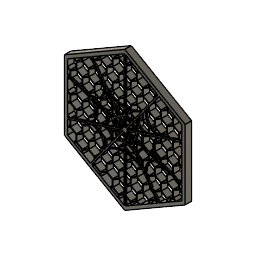
Honey Comb and Web Spider (1) (Autodesk Fusion 360 design; units mm, degrees)
Autodesk Fusion 360 part; units mm, degrees
(part 1 of 3)
sketch "Sketch1" plane through (0, 0, 0) normal (0, 1, 0) x (1, 0, 0)
  line L0 (0, 0) -> (-86.603, 0) construction
  line L1 (-86.603, 0) -> (-86.603, 50) construction
  line L2 (-86.603, 50) -> (-86.603, -50)
  line L3 (-86.603, -50) -> (-0.0005, -100)
  line L4 (-0.0005, -100) -> (86.6021, -50)
  line L5 (86.6021, -50) -> (86.6021, 50)
  line L6 (86.6021, 50) -> (-0.0005, 100)
  line L7 (-0.0005, 100) -> (-86.603, 50)
  line L8 (-0.0005, -100) -> (-0.0005, 0) construction
  line L9 (-0.0005, 0) -> (8.6598, 0) construction
  line L10 (8.6598, 0) -> (8.6598, 5) construction
  line L11 (8.6598, 5) -> (-0.0004, 10)
  line L12 (-0.0004, 10) -> (-8.6607, 5)
  line L13 (-8.6607, 5) -> (-8.6607, -5)
  line L14 (-8.6607, -5) -> (-0.0004, -10)
  line L15 (-0.0004, -10) -> (8.6598, -5)
  line L16 (8.6598, -5) -> (8.6598, 5)
  line L17 (-0.0004, -10) -> (0.4996, -10.866) construction
  line L18 (0.4996, -10.866) -> (0.4996, -20.866)
  line L19 (0.4996, -20.866) -> (9.1598, -25.866)
  line L20 (9.1598, -25.866) -> (17.8201, -20.866)
  line L21 (17.8201, -20.866) -> (17.8201, -10.866)
  line L22 (17.8201, -10.866) -> (9.1598, -5.866)
  line L23 (9.1598, -5.866) -> (0.4996, -10.866)
  line L24 (9.1598, -5.866) -> (9.6598, -5) construction
  line L25 (9.6598, -5) -> (8.6598, -5) construction
  line L26 (9.6598, -5) -> (18.3201, -10)
  line L27 (18.3201, -10) -> (26.9803, -5)
  line L28 (26.9803, -5) -> (26.9803, 5)
  line L29 (26.9803, 5) -> (18.3201, 10)
  line L30 (18.3201, 10) -> (9.6598, 5)
  line L31 (9.6598, 5) -> (9.6598, -5)
  line L32 (18.3201, -10) -> (18.8201, -10.866) construction
  line L33 (18.3201, -10) -> (19.3201, -10) construction
  line L34 (18.8201, -10.866) -> (17.8201, -10.866) construction
  line L35 (26.9803, -5) -> (27.9803, -5) construction
  line L36 (17.8201, -20.866) -> (18.8201, -20.866) construction
  line L37 (18.8201, -20.866) -> (27.4803, -25.866)
  line L38 (27.4803, -25.866) -> (36.1406, -20.866)
  line L39 (36.1406, -20.866) -> (36.1406, -10.866)
  line L40 (36.1406, -10.866) -> (27.4803, -5.866)
  line L41 (27.4803, -5.866) -> (18.8201, -10.866)
  line L42 (18.8201, -10.866) -> (18.8201, -20.866)
  line L43 (27.9803, -5) -> (36.6406, -10)
  line L44 (36.6406, -10) -> (45.3009, -5)
  line L45 (45.3009, -5) -> (45.3009, 5)
  line L46 (45.3009, 5) -> (36.6406, 10)
  line L47 (36.6406, 10) -> (27.9803, 5)
  line L48 (27.9803, 5) -> (27.9803, -5)
  line L49 (17.8201, -20.866) -> (18.3201, -21.7321) construction
  line L50 (18.3201, -21.7321) -> (9.6598, -26.7321) construction
  line L51 (18.3201, -21.7321) -> (9.6598, -26.7321)
  line L52 (9.6598, -26.7321) -> (9.6598, -36.7321)
  line L53 (9.6598, -36.7321) -> (18.3201, -41.7321)
  line L54 (18.3201, -41.7321) -> (26.9803, -36.7321)
  line L55 (26.9803, -36.7321) -> (26.9803, -26.7321)
  line L56 (26.9803, -26.7321) -> (18.3201, -21.7321)
  line L57 (9.6598, -26.7321) -> (8.6598, -26.7321) construction
  line L58 (26.9803, -26.7321) -> (27.9803, -26.7321) construction
  line L59 (36.1406, -20.866) -> (37.1406, -20.866) construction
  line L60 (45.3009, -5) -> (46.3009, -5) construction
  line L61 (46.3009, -5) -> (54.9611, -10)
  line L62 (54.9611, -10) -> (63.6214, -5)
  line L63 (63.6214, -5) -> (63.6214, 5)
  line L64 (63.6214, 5) -> (54.9611, 10)
  line L65 (54.9611, 10) -> (46.3009, 5)
  line L66 (46.3009, 5) -> (46.3009, -5)
  line L67 (37.1406, -20.866) -> (45.8009, -25.866)
  line L68 (45.8009, -25.866) -> (54.4611, -20.866)
  line L69 (54.4611, -20.866) -> (54.4611, -10.866)
  line L70 (54.4611, -10.866) -> (45.8009, -5.866)
  line L71 (45.8009, -5.866) -> (37.1406, -10.866)
  line L72 (37.1406, -10.866) -> (37.1406, -20.866)
  line L73 (27.9803, -26.7321) -> (27.9803, -36.7321)
  line L74 (27.9803, -36.7321) -> (36.6406, -41.7321)
  line L75 (36.6406, -41.7321) -> (45.3009, -36.7321)
  line L76 (45.3009, -36.7321) -> (45.3009, -26.7321)
  line L77 (45.3009, -26.7321) -> (36.6406, -21.7321)
  line L78 (36.6406, -21.7321) -> (27.9803, -26.7321)
  line L79 (8.6598, -26.7321) -> (-0.0004, -21.7321)
  line L80 (-0.0004, -21.7321) -> (-8.6607, -26.7321)
  line L81 (-8.6607, -26.7321) -> (-8.6607, -36.7321)
  line L82 (-8.6607, -36.7321) -> (-0.0004, -41.7321)
  line L83 (-0.0004, -41.7321) -> (8.6598, -36.7321)
  line L84 (8.6598, -36.7321) -> (8.6598, -26.7321)
  line L85 (8.6598, -36.7321) -> (9.1598, -37.5981) construction
  line L86 (26.9803, -36.7321) -> (27.4803, -37.5981) construction
  line L87 (45.3009, -36.7321) -> (45.8009, -37.5981) construction
  line L88 (45.3009, -36.7321) -> (46.3009, -36.7321) construction
  line L89 (54.4611, -20.866) -> (55.4611, -20.866) construction
  line L90 (63.6214, -5) -> (64.6214, -5) construction
  line L91 (64.6214, -5) -> (73.2816, -10)
  line L92 (73.2816, -10) -> (81.9419, -5)
  line L93 (81.9419, -5) -> (81.9419, 5)
  line L94 (81.9419, 5) -> (73.2816, 10)
  line L95 (73.2816, 10) -> (64.6214, 5)
  line L96 (64.6214, 5) -> (64.6214, -5)
  line L97 (55.4611, -20.866) -> (64.1214, -25.866)
  line L98 (64.1214, -25.866) -> (72.7816, -20.866)
  line L99 (72.7816, -20.866) -> (72.7816, -10.866)
  line L100 (72.7816, -10.866) -> (64.1214, -5.866)
  line L101 (64.1214, -5.866) -> (55.4611, -10.866)
  line L102 (55.4611, -10.866) -> (55.4611, -20.866)
  line L103 (46.3009, -36.7321) -> (54.9611, -41.7321)
  line L104 (54.9611, -41.7321) -> (63.6214, -36.7321)
  line L105 (63.6214, -36.7321) -> (63.6214, -26.7321)
  line L106 (63.6214, -26.7321) -> (54.9611, -21.7321)
  line L107 (54.9611, -21.7321) -> (46.3009, -26.7321)
  line L108 (46.3009, -26.7321) -> (46.3009, -36.7321)
  line L109 (45.8009, -37.5981) -> (37.1406, -42.5981)
  line L110 (37.1406, -42.5981) -> (37.1406, -52.5981)
  line L111 (37.1406, -52.5981) -> (45.8009, -57.5981)
  line L112 (45.8009, -57.5981) -> (54.4611, -52.5981)
  line L113 (54.4611, -52.5981) -> (54.4611, -42.5981)
  line L114 (54.4611, -42.5981) -> (45.8009, -37.5981)
  line L115 (45.8009, -37.5981) -> (55.8009, -37.5981) construction
  line L116 (27.4803, -37.5981) -> (18.8201, -42.5981)
  line L117 (18.8201, -42.5981) -> (18.8201, -52.5981)
  line L118 (18.8201, -52.5981) -> (27.4803, -57.5981)
  line L119 (27.4803, -57.5981) -> (36.1406, -52.5981)
  line L120 (36.1406, -52.5981) -> (36.1406, -42.5981)
  line L121 (36.1406, -42.5981) -> (27.4803, -37.5981)
  line L122 (27.4803, -37.5981) -> (37.4803, -37.5981) construction
  line L123 (9.1598, -37.5981) -> (0.4996, -42.5981)
  line L124 (0.4996, -42.5981) -> (0.4996, -52.5981)
  line L125 (0.4996, -52.5981) -> (9.1598, -57.5981)
  line L126 (9.1598, -57.5981) -> (17.8201, -52.5981)
  line L127 (17.8201, -52.5981) -> (17.8201, -42.5981)
  line L128 (17.8201, -42.5981) -> (9.1598, -37.5981)
  line L129 (9.1598, -37.5981) -> (19.1598, -37.5981) construction
  line L130 (9.1598, -57.5981) -> (9.6598, -58.4641) construction
  line L131 (9.6598, -58.4641) -> (8.6598, -58.4641) construction
  line L132 (17.8201, -52.5981) -> (18.3201, -53.4641) construction
  line L133 (36.1406, -52.5981) -> (36.6406, -53.4641) construction
  line L134 (36.1406, -52.5981) -> (37.1406, -52.5981) construction
  line L135 (54.4611, -52.5981) -> (55.4611, -52.5981) construction
  line L136 (63.6214, -36.7321) -> (64.6214, -36.7321) construction
  line L137 (72.7816, -20.866) -> (73.7816, -20.866) construction
  line L138 (81.9419, -5) -> (82.9419, -5) construction
  line L139 (82.9419, -5) -> (86.6021, -7.1132)
  line L140 (86.6021, 7.1132) -> (82.9419, 5)
  line L141 (82.9419, 5) -> (82.9419, -5)
  line L142 (73.7816, -20.866) -> (82.4419, -25.866)
  line L143 (82.4419, -25.866) -> (86.6021, -23.4641)
  line L144 (86.6021, -8.2679) -> (82.4419, -5.866)
  line L145 (82.4419, -5.866) -> (73.7816, -10.866)
  line L146 (73.7816, -10.866) -> (73.7816, -20.866)
  line L147 (64.6214, -36.7321) -> (73.2816, -41.7321)
  line L148 (73.2816, -41.7321) -> (81.9419, -36.7321)
  line L149 (81.9419, -36.7321) -> (81.9419, -26.7321)
  line L150 (81.9419, -26.7321) -> (73.2816, -21.7321)
  line L151 (73.2816, -21.7321) -> (64.6214, -26.7321)
  line L152 (64.6214, -26.7321) -> (64.6214, -36.7321)
  line L153 (55.4611, -52.5981) -> (64.1214, -57.5981)
  line L154 (64.1214, -57.5981) -> (72.7816, -52.5981)
  line L155 (72.7816, -52.5981) -> (72.7816, -42.5981)
  line L156 (72.7816, -42.5981) -> (64.1214, -37.5981)
  line L157 (64.1214, -37.5981) -> (55.4611, -42.5981)
  line L158 (55.4611, -42.5981) -> (55.4611, -52.5981)
  line L159 (36.6406, -53.4641) -> (27.9803, -58.4641)
  line L160 (27.9803, -58.4641) -> (27.9803, -68.4641)
  line L161 (27.9803, -68.4641) -> (36.6406, -73.4641)
  line L162 (36.6406, -73.4641) -> (45.3009, -68.4641)
  line L163 (45.3009, -68.4641) -> (45.3009, -58.4641)
  line L164 (45.3009, -58.4641) -> (36.6406, -53.4641)
  line L165 (36.6406, -53.4641) -> (46.6406, -53.4641) construction
  line L166 (18.3201, -53.4641) -> (9.6598, -58.4641)
  line L167 (9.6598, -58.4641) -> (9.6598, -68.4641)
  line L168 (9.6598, -68.4641) -> (18.3201, -73.4641)
  line L169 (18.3201, -73.4641) -> (26.9803, -68.4641)
  line L170 (26.9803, -68.4641) -> (26.9803, -58.4641)
  line L171 (26.9803, -58.4641) -> (18.3201, -53.4641)
  line L172 (18.3201, -53.4641) -> (28.3201, -53.4641) construction
  line L173 (8.6598, -58.4641) -> (-0.0004, -53.4641)
  line L174 (-0.0004, -53.4641) -> (-8.6607, -58.4641)
  line L175 (-8.6607, -58.4641) -> (-8.6607, -68.4641)
  line L176 (-8.6607, -68.4641) -> (-0.0004, -73.4641)
  line L177 (-0.0004, -73.4641) -> (8.6598, -68.4641)
  line L178 (8.6598, -68.4641) -> (8.6598, -58.4641)
  line L179 (8.6598, -58.4641) -> (18.6598, -58.4641) construction
  line L180 (8.6598, -68.4641) -> (9.1598, -69.3301) construction
  line L181 (26.9803, -68.4641) -> (27.4803, -69.3301) construction
  line L182 (26.9803, -68.4641) -> (27.9803, -68.4641) construction
  line L183 (45.3009, -68.4641) -> (45.8009, -69.3301) construction
  line L184 (45.8009, -69.3301) -> (46.3009, -68.4641) construction
  line L185 (46.3009, -68.4641) -> (45.3009, -68.4641) construction
  line L186 (72.7816, -52.5981) -> (73.7816, -52.5981) construction
  line L187 (81.9419, -36.7321) -> (82.9419, -36.7321) construction
  line L188 (72.7816, -52.5981) -> (73.2816, -53.4641) construction
  line L189 (72.7816, -52.5981) -> (73.7816, -52.5981) construction
  line L190 (73.7816, -52.5981) -> (77.9418, -55)
  line L191 (86.6021, -40) -> (82.4419, -37.5981)
  line L192 (82.4419, -37.5981) -> (73.7816, -42.5981)
  line L193 (73.7816, -42.5981) -> (73.7816, -52.5981)
  line L194 (82.9419, -36.7321) -> (86.6021, -38.8453)
  line L195 (86.6021, -24.6188) -> (82.9419, -26.7321)
  line L196 (82.9419, -26.7321) -> (82.9419, -36.7321)
  line L197 (73.2816, -53.4641) -> (64.6214, -58.4641)
  line L198 (64.6214, -58.4641) -> (64.6214, -62.6906)
  line L199 (76.9418, -55.5773) -> (73.2816, -53.4641)
  line L200 (73.2816, -53.4641) -> (83.2816, -53.4641) construction
  line L201 (46.3009, -68.4641) -> (50.4611, -70.866)
  line L202 (63.6214, -63.2679) -> (63.6214, -58.4641)
  line L203 (63.6214, -58.4641) -> (54.9611, -53.4641)
  line L204 (54.9611, -53.4641) -> (46.3009, -58.4641)
  line L205 (46.3009, -58.4641) -> (46.3009, -68.4641)
  line L206 (45.8009, -69.3301) -> (37.1406, -74.3301)
  line L207 (37.1406, -74.3301) -> (37.1406, -78.5566)
  line L208 (49.4611, -71.4434) -> (45.8009, -69.3301)
  line L209 (45.8009, -69.3301) -> (55.8009, -69.3301) construction
  line L210 (27.4803, -69.3301) -> (18.8201, -74.3301)
  line L211 (18.8201, -74.3301) -> (18.8201, -84.3301)
  line L212 (18.8201, -84.3301) -> (22.9803, -86.732)
  line L213 (36.1406, -79.1339) -> (36.1406, -74.3301)
  line L214 (36.1406, -74.3301) -> (27.4803, -69.3301)
  line L215 (27.4803, -69.3301) -> (37.4803, -69.3301) construction
  line L216 (9.1598, -69.3301) -> (0.4996, -74.3301)
  line L217 (0.4996, -74.3301) -> (0.4996, -84.3301)
  line L218 (0.4996, -84.3301) -> (9.1598, -89.3301)
  line L219 (9.1598, -89.3301) -> (17.8201, -84.3301)
  line L220 (17.8201, -84.3301) -> (17.8201, -74.3301)
  line L221 (17.8201, -74.3301) -> (9.1598, -69.3301)
  line L222 (9.1598, -69.3301) -> (19.1598, -69.3301) construction
  line L223 (9.1598, -89.3301) -> (9.6598, -90.1962) construction
  line L224 (9.1598, -89.3301) -> (10.1598, -89.3301) construction
  line L225 (9.6598, -90.1962) -> (8.6598, -90.1962) construction
  line L226 (9.6598, -90.1962) -> (9.6598, -94.4226)
  line L227 (21.9803, -87.3094) -> (18.3201, -85.1962)
  line L228 (18.3201, -85.1962) -> (9.6598, -90.1962)
  line L229 (9.6598, -90.1962) -> (19.6598, -90.1962) construction
  line L230 (8.6598, -90.1962) -> (-0.0004, -85.1962)
  line L231 (-0.0004, -85.1962) -> (-8.6607, -90.1962)
  line L232 (-8.6607, -90.1962) -> (-8.6607, -95)
  line L233 (8.6598, -95) -> (8.6598, -90.1962)
  line L234 (8.6598, -90.1962) -> (18.6598, -90.1962) construction
  line L235 (-36.1415, -52.5981) -> (-37.1415, -52.5981) construction
  line L236 (-54.462, -52.5981) -> (-55.462, -52.5981) construction
  line L237 (-45.3018, -68.4641) -> (-45.8018, -69.3301) construction
  line L238 (-45.8018, -37.5981) -> (-37.1415, -42.5981)
  line L239 (-36.1415, -52.5981) -> (-36.1415, -42.5981)
  line L240 (-45.8018, -37.5981) -> (-55.8018, -37.5981) construction
  line L241 (-36.1415, -79.1339) -> (-36.1415, -74.3301)
  line L242 (-82.9428, 5) -> (-82.9428, -5)
  line L243 (-54.462, -52.5981) -> (-54.462, -42.5981)
  line L244 (-36.1415, -52.5981) -> (-36.6415, -53.4641) construction
  line L245 (-49.462, -71.4434) -> (-45.8018, -69.3301)
  line L246 (-37.1415, -74.3301) -> (-37.1415, -78.5566)
  line L247 (-45.3018, -58.4641) -> (-36.6415, -53.4641)
  line L248 (-54.962, -53.4641) -> (-46.3018, -58.4641)
  line L249 (-46.3018, -58.4641) -> (-46.3018, -68.4641)
  line L250 (-27.9813, 5) -> (-27.9813, -5)
  line L251 (-45.3018, -68.4641) -> (-45.3018, -58.4641)
  line L252 (-36.6415, -53.4641) -> (-46.6415, -53.4641) construction
  line L253 (-45.8018, -57.5981) -> (-54.462, -52.5981)
  line L254 (-46.3018, -68.4641) -> (-50.462, -70.866)
  line L255 (-46.3018, -68.4641) -> (-45.3018, -68.4641) construction
  line L256 (-45.8018, -69.3301) -> (-55.8018, -69.3301) construction
  line L257 (-55.462, -42.5981) -> (-55.462, -52.5981)
  line L258 (8.6597, 5) -> (8.6597, -5)
  line L259 (-54.462, -42.5981) -> (-45.8018, -37.5981)
  line L260 (-37.1415, -52.5981) -> (-45.8018, -57.5981)
  line L261 (-0.0005, -100) -> (-0.0005, 0) construction
  line L262 (-8.6608, -5) -> (-8.6608, 5)
  line L263 (-64.6223, 5) -> (-64.6223, -5)
  line L264 (-72.7825, -52.5981) -> (-72.7825, -42.5981)
  line L265 (-63.6223, -63.2679) -> (-63.6223, -58.4641)
  line L266 (-72.7825, -52.5981) -> (-73.7825, -52.5981) construction
  line L267 (-82.9428, -36.7321) -> (-86.603, -38.8453)
  line L268 (-86.603, -40) -> (-82.4428, -37.5981)
  line L269 (-73.2825, -53.4641) -> (-64.6223, -58.4641)
  line L270 (-63.6223, -36.7321) -> (-64.6223, -36.7321) construction
  line L271 (-72.7825, -52.5981) -> (-73.7825, -52.5981) construction
  line L272 (-73.2825, -53.4641) -> (-83.2825, -53.4641) construction
  line L273 (-72.7825, -42.5981) -> (-64.1223, -37.5981)
  line L274 (-76.9428, -55.5773) -> (-73.2825, -53.4641)
  line L275 (-73.7825, -52.5981) -> (-77.9428, -55)
  line L276 (-81.9428, -36.7321) -> (-82.9428, -36.7321) construction
  line L277 (-64.6223, -36.7321) -> (-73.2825, -41.7321)
  line L278 (-73.7825, -42.5981) -> (-73.7825, -52.5981)
  line L279 (-64.1223, -57.5981) -> (-72.7825, -52.5981)
  line L280 (-64.6223, -58.4641) -> (-64.6223, -62.6906)
  line L281 (-72.7825, -52.5981) -> (-73.2825, -53.4641) construction
  line L282 (-82.4428, -37.5981) -> (-73.7825, -42.5981)
  line L283 (-73.2825, -41.7321) -> (-81.9428, -36.7321)
  line L284 (-26.9813, -26.7321) -> (-18.321, -21.7321)
  line L285 (-27.4813, -37.5981) -> (-18.821, -42.5981)
  line L286 (-17.821, -20.866) -> (-17.821, -10.866)
  line L287 (-18.321, -21.7321) -> (-9.6608, -26.7321) construction
  line L288 (-18.321, -10) -> (-26.9813, -5)
  line L289 (-9.6608, -5) -> (-8.6608, -5) construction
  line L290 (-26.9813, -68.4641) -> (-26.9813, -58.4641)
  line L291 (-18.321, -53.4641) -> (-28.321, -53.4641) construction
  line L292 (-26.9813, -36.7321) -> (-27.4813, -37.5981) construction
  line L293 (-27.4813, -69.3301) -> (-18.821, -74.3301)
  line L294 (-18.321, -10) -> (-19.321, -10) construction
  line L295 (-17.821, -20.866) -> (-18.321, -21.7321) construction
  line L296 (-17.821, -74.3301) -> (-9.1608, -69.3301)
  line L297 (-17.821, -20.866) -> (-18.821, -20.866) construction
  line L298 (-18.821, -42.5981) -> (-18.821, -52.5981)
  line L299 (-9.1608, -25.866) -> (-17.821, -20.866)
  line L300 (-9.1608, -69.3301) -> (-19.1608, -69.3301) construction
  line L301 (-18.821, -84.3301) -> (-22.9812, -86.732)
  line L302 (-9.6608, -58.4641) -> (-8.6608, -58.4641) construction
  line L303 (-18.321, -21.7321) -> (-9.6608, -26.7321)
  line L304 (-8.6608, -36.7321) -> (-9.1608, -37.5981) construction
  line L305 (-8.6608, -68.4641) -> (-8.6608, -58.4641)
  line L306 (-17.821, -42.5981) -> (-9.1608, -37.5981)
  line L307 (-9.6608, -58.4641) -> (-9.6608, -68.4641)
  line L308 (-26.9813, -68.4641) -> (-27.4813, -69.3301) construction
  line L309 (-9.6608, -36.7321) -> (-18.321, -41.7321)
  line L310 (-18.321, -10) -> (-18.821, -10.866) construction
  line L311 (-17.821, -52.5981) -> (-17.821, -42.5981)
  line L312 (-9.1608, -57.5981) -> (-9.6608, -58.4641) construction
  line L313 (-18.321, -53.4641) -> (-9.6608, -58.4641)
  line L314 (-26.9813, -26.7321) -> (-27.9813, -26.7321) construction
  line L315 (-18.821, -10.866) -> (-18.821, -20.866)
  line L316 (-26.9813, -68.4641) -> (-27.9813, -68.4641) construction
  line L317 (-18.821, -52.5981) -> (-27.4813, -57.5981)
  line L318 (-81.9428, -5) -> (-81.9428, 5)
  line L319 (-36.6415, -10) -> (-45.3018, -5)
  line L320 (-86.603, -8.2679) -> (-82.4428, -5.866)
  line L321 (-82.4428, -5.866) -> (-73.7825, -10.866)
  line L322 (-26.9813, -5) -> (-26.9813, 5)
  line L323 (-9.6608, 5) -> (-9.6608, -5)
  line L324 (-36.1415, -20.866) -> (-37.1415, -20.866) construction
  line L325 (-36.1415, -20.866) -> (-36.1415, -10.866)
  line L326 (-72.7825, -10.866) -> (-64.1223, -5.866)
  line L327 (-73.7825, -10.866) -> (-73.7825, -20.866)
  line L328 (-45.3018, -5) -> (-46.3018, -5) construction
  line L329 (-55.462, -10.866) -> (-55.462, -20.866)
  line L330 (-63.6223, -5) -> (-63.6223, 5)
  line L331 (-55.462, -20.866) -> (-64.1223, -25.866)
  line L332 (-0.0005, -41.7321) -> (-8.6608, -36.7321)
  line L333 (-46.3018, 5) -> (-46.3018, -5)
  line L334 (-81.9428, -26.7321) -> (-73.2825, -21.7321)
  line L335 (-37.1415, -10.866) -> (-37.1415, -20.866)
  line L336 (-45.8018, -5.866) -> (-37.1415, -10.866)
  line L337 (-45.3018, -5) -> (-45.3018, 5)
  line L338 (-8.6608, 0) -> (-8.6608, 5) construction
  line L339 (-45.3018, -26.7321) -> (-36.6415, -21.7321)
  line L340 (-63.6223, -5) -> (-64.6223, -5) construction
  line L341 (-37.1415, -20.866) -> (-45.8018, -25.866)
  line L342 (-54.962, -10) -> (-63.6223, -5)
  line L343 (-73.7825, -20.866) -> (-82.4428, -25.866)
  line L344 (-8.6608, 5) -> (-0.0005, 10)
  line L345 (-86.603, -24.6188) -> (-82.9428, -26.7321)
  line L346 (-82.9428, -5) -> (-86.603, -7.1132)
  line L347 (-45.8018, -69.3301) -> (-37.1415, -74.3301)
  line L348 (-45.8018, -69.3301) -> (-46.3018, -68.4641) construction
  line L349 (-36.6415, -41.7321) -> (-45.3018, -36.7321)
  line L350 (-54.962, -41.7321) -> (-63.6223, -36.7321)
  line L351 (-45.3018, -36.7321) -> (-46.3018, -36.7321) construction
  line L352 (-64.1223, -37.5981) -> (-55.462, -42.5981)
  line L353 (-63.6223, -58.4641) -> (-54.962, -53.4641)
  line L354 (-55.462, -52.5981) -> (-64.1223, -57.5981)
  line L355 (-81.9428, -36.7321) -> (-81.9428, -26.7321)
  line L356 (-64.6223, -26.7321) -> (-64.6223, -36.7321)
  line L357 (-0.0005, -10) -> (-0.5005, -10.866) construction
  line L358 (-36.6415, -21.7321) -> (-27.9813, -26.7321)
  line L359 (-36.1415, -74.3301) -> (-27.4813, -69.3301)
  line L360 (-27.4813, -57.5981) -> (-36.1415, -52.5981)
  line L361 (8.6597, -36.7321) -> (-0.0005, -41.7321)
  line L362 (-0.0005, -21.7321) -> (8.6597, -26.7321)
  line L363 (-27.9813, -36.7321) -> (-36.6415, -41.7321)
  line L364 (-63.6223, -26.7321) -> (-54.962, -21.7321)
  line L365 (8.6597, -58.4641) -> (8.6597, -68.4641)
  line L366 (8.6597, -26.7321) -> (8.6597, -36.7321)
  line L367 (-27.9813, -5) -> (-36.6415, -10)
  line L368 (8.6597, -68.4641) -> (-0.0005, -73.4641)
  line L369 (-46.3018, -26.7321) -> (-46.3018, -36.7321)
  line L370 (-0.0005, -85.1962) -> (8.6597, -90.1962)
  line L371 (-27.4813, -25.866) -> (-36.1415, -20.866)
  line L372 (-0.5005, -10.866) -> (-0.5005, -20.866)
  line L373 (-63.6223, -36.7321) -> (-63.6223, -26.7321)
  line L374 (-0.5005, -74.3301) -> (-0.5005, -84.3301)
  line L375 (8.6597, -90.1962) -> (8.6597, -95)
  line L376 (-36.1415, -42.5981) -> (-27.4813, -37.5981)
  line L377 (8.6597, -5) -> (-0.0005, -10)
  line L378 (-27.4813, -69.3301) -> (-37.4813, -69.3301) construction
  line L379 (-45.3018, -36.7321) -> (-45.3018, -26.7321)
  line L380 (-82.9428, -26.7321) -> (-82.9428, -36.7321)
  line L381 (-36.1415, -10.866) -> (-27.4813, -5.866)
  line L382 (-0.0005, -53.4641) -> (8.6597, -58.4641)
  line L383 (-27.4813, -37.5981) -> (-37.4813, -37.5981) construction
  line L384 (-27.9813, -68.4641) -> (-36.6415, -73.4641)
  line L385 (-36.6415, -53.4641) -> (-27.9813, -58.4641)
  line L386 (-9.6608, -26.7321) -> (-9.6608, -36.7321)
  line L387 (-18.321, -73.4641) -> (-26.9813, -68.4641)
  line L388 (-8.6608, -58.4641) -> (-18.6608, -58.4641) construction
  line L389 (-18.321, -85.1962) -> (-9.6608, -90.1962)
  line L390 (-8.6608, -36.7321) -> (-8.6608, -26.7321)
  line L391 (-26.9813, -36.7321) -> (-26.9813, -26.7321)
  line L392 (-8.6608, -90.1962) -> (-18.6608, -90.1962) construction
  line L393 (-17.821, -52.5981) -> (-18.321, -53.4641) construction
  line L394 (-9.1608, -57.5981) -> (-17.821, -52.5981)
  line L395 (-9.1608, -5.866) -> (-9.6608, -5) construction
  line L396 (-26.9813, -58.4641) -> (-18.321, -53.4641)
  line L397 (-9.6608, -5) -> (-18.321, -10)
  line L398 (-8.6608, -68.4641) -> (-9.1608, -69.3301) construction
  line L399 (-27.9813, -26.7321) -> (-27.9813, -36.7321)
  line L400 (-9.6608, -90.1962) -> (-9.6608, -94.4226)
  line L401 (-21.9812, -87.3094) -> (-18.321, -85.1962)
  line L402 (-9.6608, -90.1962) -> (-8.6608, -90.1962) construction
  line L403 (-9.6608, -68.4641) -> (-18.321, -73.4641)
  line L404 (-27.9813, -58.4641) -> (-27.9813, -68.4641)
  line L405 (-17.821, -84.3301) -> (-17.821, -74.3301)
  line L406 (-27.4813, -5.866) -> (-18.821, -10.866)
  line L407 (-9.1608, -89.3301) -> (-10.1608, -89.3301) construction
  line L408 (-18.821, -10.866) -> (-17.821, -10.866) construction
  line L409 (-9.6608, -90.1962) -> (-19.6608, -90.1962) construction
  line L410 (-8.6608, -95) -> (-8.6608, -90.1962)
  line L411 (-18.821, -20.866) -> (-27.4813, -25.866)
  line L412 (-9.1608, -89.3301) -> (-9.6608, -90.1962) construction
  line L413 (-26.9813, -5) -> (-27.9813, -5) construction
  line L414 (-18.821, -74.3301) -> (-18.821, -84.3301)
  line L415 (-18.321, -41.7321) -> (-26.9813, -36.7321)
  line L416 (-9.1608, -89.3301) -> (-17.821, -84.3301)
  line L417 (-17.821, -10.866) -> (-9.1608, -5.866)
  line L418 (-9.6608, -26.7321) -> (-8.6608, -26.7321) construction
  line L419 (-45.3018, 5) -> (-36.6415, 10)
  line L420 (-73.2825, 10) -> (-64.6223, 5)
  line L421 (-81.9428, 5) -> (-73.2825, 10)
  line L422 (-0.0005, 10) -> (8.6597, 5)
  line L423 (-0.0005, -100) -> (-86.603, -50)
  line L424 (-86.603, 7.1132) -> (-82.9428, 5)
  line L425 (-18.321, 10) -> (-9.6608, 5)
  line L426 (-8.6608, -90.1962) -> (-0.0005, -85.1962)
  line L427 (-26.9813, 5) -> (-18.321, 10)
  line L428 (-0.5005, -52.5981) -> (-9.1608, -57.5981)
  line L429 (-72.7825, -20.866) -> (-73.7825, -20.866) construction
  line L430 (-64.1223, -5.866) -> (-55.462, -10.866)
  line L431 (-64.1223, -25.866) -> (-72.7825, -20.866)
  line L432 (-64.6223, -5) -> (-73.2825, -10)
  line L433 (-54.462, -20.866) -> (-55.462, -20.866) construction
  line L434 (-63.6223, 5) -> (-54.962, 10)
  line L435 (-0.0005, -73.4641) -> (-8.6608, -68.4641)
  line L436 (-54.962, 10) -> (-46.3018, 5)
  line L437 (-54.462, -10.866) -> (-45.8018, -5.866)
  line L438 (-36.6415, 10) -> (-27.9813, 5)
  line L439 (-82.4428, -25.866) -> (-86.603, -23.4641)
  line L440 (-0.0005, -10) -> (-8.6608, -5)
  line L441 (-72.7825, -20.866) -> (-72.7825, -10.866)
  line L442 (-0.5005, -84.3301) -> (-9.1608, -89.3301)
  line L443 (-73.2825, -10) -> (-81.9428, -5)
  line L444 (-9.1608, -69.3301) -> (-0.5005, -74.3301)
  line L445 (-45.8018, -25.866) -> (-54.462, -20.866)
  line L446 (-0.0005, 0) -> (-8.6608, 0) construction
  line L447 (-81.9428, -5) -> (-82.9428, -5) construction
  line L448 (-9.1608, -5.866) -> (-0.5005, -10.866)
  line L449 (-8.6608, -26.7321) -> (-0.0005, -21.7321)
  line L450 (-73.2825, -21.7321) -> (-64.6223, -26.7321)
  line L451 (-0.5005, -20.866) -> (-9.1608, -25.866)
  line L452 (-46.3018, -5) -> (-54.962, -10)
  line L453 (-54.962, -21.7321) -> (-46.3018, -26.7321)
  line L454 (-54.462, -20.866) -> (-54.462, -10.866)
  line L455 (-8.6608, -58.4641) -> (-0.0005, -53.4641)
  line L456 (-0.5005, -42.5981) -> (-0.5005, -52.5981)
  line L457 (-9.1608, -37.5981) -> (-0.5005, -42.5981)
  line L458 (-46.3018, -36.7321) -> (-54.962, -41.7321)
  line L459 (-37.1415, -42.5981) -> (-37.1415, -52.5981)
  line L460 (-45.3018, -36.7321) -> (-45.8018, -37.5981) construction
  line L461 (-36.6415, -73.4641) -> (-45.3018, -68.4641)
  line L462 (-86.603, 0) -> (86.6021, 0) construction
  line L463 (64.6214, 36.7321) -> (73.2816, 41.7321)
  line L464 (76.9418, 55.5773) -> (73.2816, 53.4641)
  line L465 (82.9419, 36.7321) -> (86.6021, 38.8453)
  line L466 (63.6214, 63.2679) -> (63.6214, 58.4641)
  line L467 (72.7816, 10.866) -> (64.1214, 5.866)
  line L468 (64.6214, 5) -> (73.2816, 10)
  line L469 (37.1406, 20.866) -> (45.8009, 25.866)
  line L470 (36.1406, 20.866) -> (37.1406, 20.866) construction
  line L471 (54.4611, 20.866) -> (54.4611, 10.866)
  line L472 (63.6214, 26.7321) -> (54.9611, 21.7321)
  line L473 (54.9611, 10) -> (63.6214, 5)
  line L474 (64.1214, 25.866) -> (72.7816, 20.866)
  line L475 (86.6021, 24.6188) -> (82.9419, 26.7321)
  line L476 (72.7816, 20.866) -> (73.7816, 20.866) construction
  line L477 (73.2816, 21.7321) -> (64.6214, 26.7321)
  line L478 (63.6214, 5) -> (64.6214, 5) construction
  line L479 (55.4611, 20.866) -> (64.1214, 25.866)
  line L480 (82.4419, 5.866) -> (73.7816, 10.866)
  line L481 (55.4611, 10.866) -> (55.4611, 20.866)
  line L482 (45.3009, 26.7321) -> (36.6406, 21.7321)
  line L483 (45.3009, 5) -> (46.3009, 5) construction
  line L484 (54.9611, 21.7321) -> (46.3009, 26.7321)
  line L485 (86.6021, 40) -> (82.4419, 37.5981)
  line L486 (72.7816, 52.5981) -> (72.7816, 42.5981)
  line L487 (-86.603, 0) -> (86.6021, 0) construction
  line L488 (73.2816, 53.4641) -> (64.6214, 58.4641)
  line L489 (73.7816, 52.5981) -> (77.9418, 55)
  line L490 (73.2816, -10) -> (64.6214, -5)
  line L491 (81.9419, 5) -> (81.9419, -5)
  line L492 (-81.9428, 5) -> (-81.9428, -5)
  line L493 (-64.6223, -5) -> (-64.6223, 5)
  line L494 (8.6597, -5) -> (8.6597, 5)
  line L495 (-45.3018, -5) -> (-36.6415, -10)
  line L496 (54.9611, -10) -> (46.3009, -5)
  line L497 (8.6598, 0) -> (8.6598, -5) construction
  line L498 (8.6598, -5) -> (-0.0004, -10)
  line L499 (63.6214, 5) -> (63.6214, -5)
  line L500 (-8.6608, -5) -> (-0.0005, -10)
  line L501 (-81.9428, -5) -> (-73.2825, -10)
  line L502 (-18.321, -10) -> (-9.6608, -5)
  line L503 (-86.603, -7.1132) -> (-82.9428, -5)
  line L504 (18.3201, -10) -> (9.6598, -5)
  line L505 (-73.2825, -10) -> (-64.6223, -5)
  line L506 (26.9803, -5) -> (18.3201, -10)
  line L507 (36.6406, -10) -> (27.9803, -5)
  line L508 (-0.0004, -10) -> (-8.6607, -5)
  line L509 (81.9419, -5) -> (73.2816, -10)
  line L510 (-26.9813, -5) -> (-18.321, -10)
  line L511 (-63.6223, -5) -> (-54.962, -10)
  line L512 (45.3009, -5) -> (36.6406, -10)
  line L513 (-54.962, -10) -> (-46.3018, -5)
  line L514 (-0.0005, -10) -> (8.6597, -5)
  line L515 (86.6021, -7.1132) -> (82.9419, -5)
  line L516 (-8.6608, 5) -> (-8.6608, -5)
  line L517 (63.6214, -5) -> (54.9611, -10)
  line L518 (-36.6415, -10) -> (-27.9813, -5)
  line L519 (-9.6608, -5) -> (-9.6608, 5)
  line L520 (45.8009, 5.866) -> (37.1406, 10.866)
  line L521 (82.9419, 5) -> (86.6021, 7.1132)
  line L522 (45.8009, 25.866) -> (54.4611, 20.866)
  line L523 (64.1214, 5.866) -> (55.4611, 10.866)
  line L524 (86.6021, 8.2679) -> (82.4419, 5.866)
  line L525 (54.4611, 20.866) -> (55.4611, 20.866) construction
  line L526 (54.4611, 10.866) -> (45.8009, 5.866)
  line L527 (36.1406, 20.866) -> (36.1406, 10.866)
  line L528 (46.3009, 5) -> (54.9611, 10)
  line L529 (82.4419, 25.866) -> (86.6021, 23.4641)
  line L530 (73.2816, 10) -> (81.9419, 5)
  line L531 (37.1406, 10.866) -> (37.1406, 20.866)
  line L532 (36.6406, 10) -> (45.3009, 5)
  line L533 (73.7816, 10.866) -> (73.7816, 20.866)
  line L534 (72.7816, 20.866) -> (72.7816, 10.866)
  line L535 (73.7816, 20.866) -> (82.4419, 25.866)
  line L536 (81.9419, 5) -> (82.9419, 5) construction
  line L537 (81.9419, 26.7321) -> (73.2816, 21.7321)
  line L538 (73.2816, 53.4641) -> (83.2816, 53.4641) construction
  line L539 (72.7816, 52.5981) -> (73.7816, 52.5981) construction
  line L540 (72.7816, 42.5981) -> (64.1214, 37.5981)
  line L541 (64.1214, 57.5981) -> (72.7816, 52.5981)
  line L542 (82.4419, 37.5981) -> (73.7816, 42.5981)
  line L543 (26.9803, 26.7321) -> (27.9803, 26.7321) construction
  line L544 (18.3201, 21.7321) -> (9.6598, 26.7321) construction
  line L545 (9.6598, 5) -> (8.6598, 5) construction
  line L546 (18.8201, 10.866) -> (18.8201, 20.866)
  line L547 (26.9803, 26.7321) -> (18.3201, 21.7321)
  line L548 (9.1598, 25.866) -> (17.8201, 20.866)
  line L549 (18.8201, 10.866) -> (17.8201, 10.866) construction
  line L550 (18.3201, 10) -> (19.3201, 10) construction
  line L551 (17.8201, 20.866) -> (18.8201, 20.866) construction
  line L552 (26.9803, 5) -> (27.9803, 5) construction
  line L553 (18.3201, 10) -> (26.9803, 5)
  line L554 (17.8201, 20.866) -> (17.8201, 10.866)
  line L555 (18.3201, 73.4641) -> (26.9803, 68.4641)
  line L556 (8.6598, 68.4641) -> (9.1598, 69.3301) construction
  line L557 (26.9803, 68.4641) -> (26.9803, 58.4641)
  line L558 (18.8201, 42.5981) -> (18.8201, 52.5981)
  line L559 (17.8201, 74.3301) -> (9.1598, 69.3301)
  line L560 (9.6598, 68.4641) -> (18.3201, 73.4641)
  line L561 (9.6598, 58.4641) -> (9.6598, 68.4641)
  line L562 (26.9803, 68.4641) -> (27.4803, 69.3301) construction
  line L563 (17.8201, 52.5981) -> (17.8201, 42.5981)
  line L564 (18.3201, 41.7321) -> (26.9803, 36.7321)
  line L565 (26.9803, 36.7321) -> (27.4803, 37.5981) construction
  line L566 (26.9803, 58.4641) -> (18.3201, 53.4641)
  line L567 (27.9803, 58.4641) -> (27.9803, 68.4641)
  line L568 (17.8201, 52.5981) -> (18.3201, 53.4641) construction
  line L569 (17.8201, 42.5981) -> (9.1598, 37.5981)
  line L570 (9.1598, 57.5981) -> (17.8201, 52.5981)
  line L571 (9.1598, 69.3301) -> (19.1598, 69.3301) construction
  line L572 (9.6598, 36.7321) -> (18.3201, 41.7321)
  line L573 (18.3201, 53.4641) -> (9.6598, 58.4641)
  line L574 (18.3201, 53.4641) -> (28.3201, 53.4641) construction
  line L575 (9.1598, 57.5981) -> (9.6598, 58.4641) construction
  line L576 (26.9803, 68.4641) -> (27.9803, 68.4641) construction
  line L577 (27.4803, 37.5981) -> (18.8201, 42.5981)
  line L578 (8.6598, 68.4641) -> (8.6598, 58.4641)
  line L579 (9.6598, 58.4641) -> (8.6598, 58.4641) construction
  line L580 (27.4803, 69.3301) -> (18.8201, 74.3301)
  line L581 (-82.9428, -5) -> (-82.9428, 5)
  line L582 (8.6597, 58.4641) -> (8.6597, 68.4641)
  line L583 (-45.3018, 5) -> (-45.3018, -5)
  line L584 (8.6598, 36.7321) -> (9.1598, 37.5981) construction
  line L585 (8.6598, 58.4641) -> (18.6598, 58.4641) construction
  line L586 (18.8201, 52.5981) -> (27.4803, 57.5981)
  line L587 (9.1598, 37.5981) -> (19.1598, 37.5981) construction
  line L588 (27.9803, -5) -> (27.9803, 5)
  line L589 (18.8201, 20.866) -> (27.4803, 25.866)
  line L590 (27.4803, 5.866) -> (18.8201, 10.866)
  line L591 (9.6598, 5) -> (18.3201, 10)
  line L592 (17.8201, 10.866) -> (9.1598, 5.866)
  line L593 (18.3201, 10) -> (18.8201, 10.866) construction
  line L594 (9.6598, 26.7321) -> (8.6598, 26.7321) construction
  line L595 (9.1598, 5.866) -> (9.6598, 5) construction
  line L596 (18.3201, 21.7321) -> (9.6598, 26.7321)
  line L597 (17.8201, 20.866) -> (18.3201, 21.7321) construction
  line L598 (46.3009, 58.4641) -> (46.3009, 68.4641)
  line L599 (36.6406, 53.4641) -> (46.6406, 53.4641) construction
  line L600 (37.1406, 74.3301) -> (37.1406, 78.5566)
  line L601 (36.1406, 52.5981) -> (37.1406, 52.5981) construction
  line L602 (54.4611, 42.5981) -> (45.8009, 37.5981)
  line L603 (46.3009, 68.4641) -> (50.4611, 70.866)
  line L604 (49.4611, 71.4434) -> (45.8009, 69.3301)
  line L605 (36.6406, 73.4641) -> (45.3009, 68.4641)
  line L606 (46.3009, 36.7321) -> (54.9611, 41.7321)
  line L607 (54.9611, 53.4641) -> (46.3009, 58.4641)
  line L608 (55.4611, 42.5981) -> (55.4611, 52.5981)
  line L609 (45.8009, 57.5981) -> (54.4611, 52.5981)
  line L610 (45.8009, 37.5981) -> (37.1406, 42.5981)
  line L611 (36.1406, 79.1339) -> (36.1406, 74.3301)
  line L612 (46.3009, 68.4641) -> (45.3009, 68.4641) construction
  line L613 (36.1406, 52.5981) -> (36.1406, 42.5981)
  line L614 (45.3009, 68.4641) -> (45.8009, 69.3301) construction
  line L615 (54.4611, 52.5981) -> (55.4611, 52.5981) construction
  line L616 (45.3009, 58.4641) -> (36.6406, 53.4641)
  line L617 (63.6214, 58.4641) -> (54.9611, 53.4641)
  line L618 (45.3009, 68.4641) -> (45.3009, 58.4641)
  line L619 (82.9419, 26.7321) -> (82.9419, 36.7321)
  line L620 (36.1406, 52.5981) -> (36.6406, 53.4641) construction
  line L621 (55.4611, 52.5981) -> (64.1214, 57.5981)
  line L622 (45.3009, 36.7321) -> (45.3009, 26.7321)
  line L623 (46.3009, 26.7321) -> (46.3009, 36.7321)
  line L624 (64.6214, 26.7321) -> (64.6214, 36.7321)
  line L625 (64.1214, 37.5981) -> (55.4611, 42.5981)
  line L626 (54.9611, 41.7321) -> (63.6214, 36.7321)
  line L627 (81.9419, 36.7321) -> (81.9419, 26.7321)
  line L628 (63.6214, 36.7321) -> (63.6214, 26.7321)
  line L629 (64.6214, 58.4641) -> (64.6214, 62.6906)
  line L630 (81.9419, 36.7321) -> (82.9419, 36.7321) construction
  line L631 (73.7816, 42.5981) -> (73.7816, 52.5981)
  line L632 (72.7816, 52.5981) -> (73.7816, 52.5981) construction
  line L633 (72.7816, 52.5981) -> (73.2816, 53.4641) construction
  line L634 (73.2816, 41.7321) -> (81.9419, 36.7321)
  line L635 (63.6214, 36.7321) -> (64.6214, 36.7321) construction
  line L636 (45.8009, 69.3301) -> (46.3009, 68.4641) construction
  line L637 (45.8009, 37.5981) -> (55.8009, 37.5981) construction
  line L638 (37.1406, 52.5981) -> (45.8009, 57.5981)
  line L639 (45.8009, 69.3301) -> (37.1406, 74.3301)
  line L640 (45.3009, 36.7321) -> (46.3009, 36.7321) construction
  line L641 (36.6406, 41.7321) -> (45.3009, 36.7321)
  line L642 (45.3009, 36.7321) -> (45.8009, 37.5981) construction
  line L643 (54.4611, 52.5981) -> (54.4611, 42.5981)
  line L644 (37.1406, 42.5981) -> (37.1406, 52.5981)
  line L645 (45.8009, 69.3301) -> (55.8009, 69.3301) construction
  line L646 (-63.6223, 5) -> (-63.6223, -5)
  line L647 (-8.6608, 0) -> (-8.6608, -5) construction
  line L648 (18.8201, 84.3301) -> (22.9803, 86.732)
  line L649 (-26.9813, 5) -> (-26.9813, -5)
  line L650 (9.6598, 90.1962) -> (19.6598, 90.1962) construction
  line L651 (9.1598, 89.3301) -> (9.6598, 90.1962) construction
  line L652 (8.6598, 5) -> (8.6598, -5)
  line L653 (8.6598, 90.1962) -> (18.6598, 90.1962) construction
  line L654 (64.6214, -5) -> (64.6214, 5)
  line L655 (82.9419, -5) -> (82.9419, 5)
  line L656 (46.3009, -5) -> (46.3009, 5)
  line L657 (9.6598, 90.1962) -> (9.6598, 94.4226)
  line L658 (8.6598, 95) -> (8.6598, 90.1962)
  line L659 (9.6598, -5) -> (9.6598, 5)
  line L660 (-27.9813, -5) -> (-27.9813, 5)
  line L661 (9.1598, 89.3301) -> (17.8201, 84.3301)
  line L662 (8.6597, 90.1962) -> (8.6597, 95)
  line L663 (8.6597, 68.4641) -> (-0.0005, 73.4641)
  line L664 (-0.0005, 53.4641) -> (8.6597, 58.4641)
  line L665 (9.6598, 90.1962) -> (8.6598, 90.1962) construction
  line L666 (9.1598, 5.866) -> (0.4996, 10.866)
  line L667 (8.6597, 26.7321) -> (8.6597, 36.7321)
  line L668 (-0.0004, 73.4641) -> (8.6598, 68.4641)
  line L669 (-8.6607, -5) -> (-8.6607, 5)
  line L670 (27.9803, 26.7321) -> (27.9803, 36.7321)
  line L671 (-0.0004, 10) -> (8.6598, 5)
  line L672 (0.4996, 52.5981) -> (9.1598, 57.5981)
  line L673 (8.6598, 26.7321) -> (-0.0004, 21.7321)
  line L674 (9.1598, 89.3301) -> (10.1598, 89.3301) construction
  line L675 (-0.0005, 0) -> (8.6598, 0) construction
  line L676 (8.6598, 36.7321) -> (8.6598, 26.7321)
  line L677 (0.4996, 84.3301) -> (9.1598, 89.3301)
  line L678 (27.4803, 37.5981) -> (37.4803, 37.5981) construction
  line L679 (17.8201, 84.3301) -> (17.8201, 74.3301)
  line L680 (27.9803, 36.7321) -> (36.6406, 41.7321)
  line L681 (8.6598, 58.4641) -> (-0.0004, 53.4641)
  line L682 (8.6597, 36.7321) -> (-0.0005, 41.7321)
  line L683 (-46.3018, -5) -> (-46.3018, 5)
  line L684 (45.3009, 5) -> (45.3009, -5)
  line L685 (36.6406, 53.4641) -> (27.9803, 58.4641)
  line L686 (26.9803, 5) -> (26.9803, -5)
  line L687 (8.6598, 90.1962) -> (-0.0004, 85.1962)
  line L688 (18.3201, 85.1962) -> (9.6598, 90.1962)
  line L689 (21.9803, 87.3094) -> (18.3201, 85.1962)
  line L690 (18.8201, 74.3301) -> (18.8201, 84.3301)
  line L691 (9.6598, 26.7321) -> (9.6598, 36.7321)
  line L692 (26.9803, 36.7321) -> (26.9803, 26.7321)
  line L693 (0.4996, 20.866) -> (9.1598, 25.866)
  line L694 (27.4803, 69.3301) -> (37.4803, 69.3301) construction
  line L695 (-73.7825, 42.5981) -> (-73.7825, 52.5981)
  line L696 (36.1406, 10.866) -> (27.4803, 5.866)
  line L697 (9.1598, 69.3301) -> (0.4996, 74.3301)
  line L698 (-0.0004, 41.7321) -> (8.6598, 36.7321)
  line L699 (-0.5005, 42.5981) -> (-0.5005, 52.5981)
  line L700 (-36.1415, 52.5981) -> (-36.1415, 42.5981)
  line L701 (-18.821, 42.5981) -> (-18.821, 52.5981)
  line L702 (-45.8018, 5.866) -> (-37.1415, 10.866)
  line L703 (36.1406, 74.3301) -> (27.4803, 69.3301)
  line L704 (-36.1415, 20.866) -> (-36.1415, 10.866)
  line L705 (8.6597, 5) -> (-0.0005, 10)
  line L706 (-0.0005, 21.7321) -> (8.6597, 26.7321)
  line L707 (-36.6415, 41.7321) -> (-45.3018, 36.7321)
  line L708 (-54.462, 52.5981) -> (-54.462, 42.5981)
  line L709 (-8.6608, 58.4641) -> (-18.6608, 58.4641) construction
  line L710 (-0.0005, 85.1962) -> (8.6597, 90.1962)
  line L711 (27.4803, 57.5981) -> (36.1406, 52.5981)
  line L712 (9.1598, 37.5981) -> (0.4996, 42.5981)
  line L713 (27.4803, 25.866) -> (36.1406, 20.866)
  line L714 (27.9803, 5) -> (36.6406, 10)
  line L715 (-72.7825, 52.5981) -> (-72.7825, 42.5981)
  line L716 (-0.0005, 100) -> (86.6021, 50)
  line L717 (36.6406, 21.7321) -> (27.9803, 26.7321)
  line L718 (36.1406, 42.5981) -> (27.4803, 37.5981)
  line L719 (0.4996, 42.5981) -> (0.4996, 52.5981)
  line L720 (-0.0005, 100) -> (-0.0005, 0) construction
  line L721 (-37.1415, 42.5981) -> (-37.1415, 52.5981)
  line L722 (27.9803, 68.4641) -> (36.6406, 73.4641)
  line L723 (-55.462, 42.5981) -> (-55.462, 52.5981)
  line L724 (-45.3018, 26.7321) -> (-36.6415, 21.7321)
  line L725 (0, 0) -> (-86.603, 0) construction
  line L726 (-17.821, 52.5981) -> (-17.821, 42.5981)
  line L727 (-0.0005, 100) -> (-0.0005, 0) construction
  line L728 (-45.8018, 37.5981) -> (-37.1415, 42.5981)
  line L729 (-36.6415, 10) -> (-45.3018, 5)
  line L730 (-37.1415, 20.866) -> (-45.8018, 25.866)
  line L731 (-17.821, 20.866) -> (-17.821, 10.866)
  line L732 (-55.462, 20.866) -> (-64.1223, 25.866)
  line L733 (-9.1608, 57.5981) -> (-9.6608, 58.4641) construction
  line L734 (-8.6608, 58.4641) -> (-0.0005, 53.4641)
  line L735 (-64.1223, 5.866) -> (-55.462, 10.866)
  line L736 (0.4996, 10.866) -> (0.4996, 20.866)
  line L737 (-46.3018, 26.7321) -> (-46.3018, 36.7321)
  line L738 (-45.8018, 37.5981) -> (-55.8018, 37.5981) construction
  line L739 (-27.9813, 68.4641) -> (-36.6415, 73.4641)
  line L740 (-18.821, 10.866) -> (-18.821, 20.866)
  line L741 (-0.5005, 52.5981) -> (-9.1608, 57.5981)
  line L742 (-46.3018, 36.7321) -> (-54.962, 41.7321)
  line L743 (-54.462, 10.866) -> (-45.8018, 5.866)
  line L744 (-18.821, 52.5981) -> (-27.4813, 57.5981)
  line L745 (-18.321, 10) -> (-26.9813, 5)
  line L746 (-63.6223, 26.7321) -> (-54.962, 21.7321)
  line L747 (-9.1608, 57.5981) -> (-17.821, 52.5981)
  line L748 (-54.962, 41.7321) -> (-63.6223, 36.7321)
  line L749 (-9.6608, 58.4641) -> (-8.6608, 58.4641) construction
  line L750 (-64.1223, 37.5981) -> (-55.462, 42.5981)
  line L751 (-0.0005, 0) -> (-8.6608, 0) construction
  line L752 (-26.9813, 58.4641) -> (-18.321, 53.4641)
  line L753 (-27.4813, 5.866) -> (-18.821, 10.866)
  line L754 (-18.321, 53.4641) -> (-28.321, 53.4641) construction
  line L755 (-54.962, 10) -> (-63.6223, 5)
  line L756 (-0.0005, 100) -> (-86.603, 50)
  line L757 (-37.1415, 10.866) -> (-37.1415, 20.866)
  line L758 (-17.821, 52.5981) -> (-18.321, 53.4641) construction
  line L759 (-0.0004, 85.1962) -> (-8.6607, 90.1962)
  line L760 (-18.321, 10) -> (-18.821, 10.866) construction
  line L761 (-82.4428, 5.866) -> (-73.7825, 10.866)
  line L762 (-72.7825, 20.866) -> (-73.7825, 20.866) construction
  line L763 (-18.821, 10.866) -> (-17.821, 10.866) construction
  line L764 (-8.6608, 95) -> (-8.6608, 90.1962)
  line L765 (-63.6223, 36.7321) -> (-64.6223, 36.7321) construction
  line L766 (-17.821, 10.866) -> (-9.1608, 5.866)
  line L767 (-81.9428, 5) -> (-82.9428, 5) construction
  line L768 (-55.462, 10.866) -> (-55.462, 20.866)
  line L769 (-63.6223, 5) -> (-64.6223, 5) construction
  line L770 (-9.6608, 68.4641) -> (-18.321, 73.4641)
  line L771 (-27.9813, 5) -> (-36.6415, 10)
  line L772 (-54.962, 21.7321) -> (-46.3018, 26.7321)
  line L773 (-73.2825, 21.7321) -> (-64.6223, 26.7321)
  line L774 (-0.0005, 10) -> (-8.6608, 5)
  line L775 (-0.0004, 10) -> (0.4996, 10.866) construction
  line L776 (-0.0004, 53.4641) -> (-8.6607, 58.4641)
  line L777 (-9.1608, 5.866) -> (-0.5005, 10.866)
  line L778 (-82.4428, 37.5981) -> (-73.7825, 42.5981)
  line L779 (-54.462, 20.866) -> (-54.462, 10.866)
  line L780 (-18.321, 53.4641) -> (-9.6608, 58.4641)
  line L781 (-45.3018, 36.7321) -> (-46.3018, 36.7321) construction
  line L782 (-9.6608, 5) -> (-8.6608, 5) construction
  line L783 (-8.6607, 5) -> (-0.0004, 10)
  line L784 (-54.462, 20.866) -> (-55.462, 20.866) construction
  line L785 (-73.7825, 10.866) -> (-73.7825, 20.866)
  line L786 (-81.9428, 36.7321) -> (-82.9428, 36.7321) construction
  line L787 (-64.6223, 36.7321) -> (-73.2825, 41.7321)
  line L788 (-8.6608, 90.1962) -> (-18.6608, 90.1962) construction
  line L789 (-72.7825, 20.866) -> (-72.7825, 10.866)
  line L790 (-45.8018, 25.866) -> (-54.462, 20.866)
  line L791 (-0.0005, 10) -> (-0.5005, 10.866) construction
  line L792 (-0.5005, 84.3301) -> (-9.1608, 89.3301)
  line L793 (-72.7825, 10.866) -> (-64.1223, 5.866)
  line L794 (-18.321, 85.1962) -> (-9.6608, 90.1962)
  line L795 (-64.6223, 26.7321) -> (-64.6223, 36.7321)
  line L796 (-82.9428, 36.7321) -> (-86.603, 38.8453)
  line L797 (-18.321, 10) -> (-19.321, 10) construction
  line L798 (-18.321, 73.4641) -> (-26.9813, 68.4641)
  line L799 (-54.462, 42.5981) -> (-45.8018, 37.5981)
  line L800 (-9.1608, 5.866) -> (-9.6608, 5) construction
  line L801 (-82.9428, 5) -> (-86.603, 7.1132)
  line L802 (-9.6608, 5) -> (-18.321, 10)
  line L803 (-73.2825, 10) -> (-81.9428, 5)
  line L804 (-26.9813, 5) -> (-27.9813, 5) construction
  line L805 (-8.6608, 68.4641) -> (-9.1608, 69.3301) construction
  line L806 (-45.3018, 5) -> (-46.3018, 5) construction
  line L807 (-64.1223, 25.866) -> (-72.7825, 20.866)
  line L808 (-45.3018, 36.7321) -> (-45.3018, 26.7321)
  line L809 (-26.9813, 68.4641) -> (-27.9813, 68.4641) construction
  line L810 (-46.3018, 5) -> (-54.962, 10)
  line L811 (-63.6223, 36.7321) -> (-63.6223, 26.7321)
  line L812 (-9.6608, 90.1962) -> (-19.6608, 90.1962) construction
  line L813 (-36.1415, 10.866) -> (-27.4813, 5.866)
  line L814 (-9.1608, 89.3301) -> (-17.821, 84.3301)
  line L815 (-64.6223, 5) -> (-73.2825, 10)
  line L816 (-86.603, 24.6188) -> (-82.9428, 26.7321)
  line L817 (-9.1608, 69.3301) -> (-0.5005, 74.3301)
  line L818 (-9.6608, 90.1962) -> (-8.6608, 90.1962) construction
  line L819 (-45.3018, 36.7321) -> (-45.8018, 37.5981) construction
  line L820 (-8.6607, 68.4641) -> (-0.0004, 73.4641)
  line L821 (-0.0005, 73.4641) -> (-8.6608, 68.4641)
  line L822 (-82.9428, 26.7321) -> (-82.9428, 36.7321)
  line L823 (-54.462, 52.5981) -> (-55.462, 52.5981) construction
  line L824 (-86.603, 40) -> (-82.4428, 37.5981)
  line L825 (-36.6415, 53.4641) -> (-27.9813, 58.4641)
  line L826 (-9.1608, 69.3301) -> (-19.1608, 69.3301) construction
  line L827 (-73.2825, 41.7321) -> (-81.9428, 36.7321)
  line L828 (-26.9813, 68.4641) -> (-27.4813, 69.3301) construction
  line L829 (-81.9428, 36.7321) -> (-81.9428, 26.7321)
  line L830 (-36.1415, 74.3301) -> (-27.4813, 69.3301)
  line L831 (-26.9813, 68.4641) -> (-26.9813, 58.4641)
  line L832 (-17.821, 74.3301) -> (-9.1608, 69.3301)
  line L833 (-18.821, 84.3301) -> (-22.9812, 86.732)
  line L834 (-81.9428, 26.7321) -> (-73.2825, 21.7321)
  line L835 (-86.603, 8.2679) -> (-82.4428, 5.866)
  line L836 (-18.821, 74.3301) -> (-18.821, 84.3301)
  line L837 (-27.4813, 57.5981) -> (-36.1415, 52.5981)
  line L838 (-27.4813, 69.3301) -> (-37.4813, 69.3301) construction
  line L839 (-8.6607, 90.1962) -> (-8.6607, 95)
  line L840 (-9.1608, 89.3301) -> (-9.6608, 90.1962) construction
  line L841 (-72.7825, 42.5981) -> (-64.1223, 37.5981)
  line L842 (-9.1608, 89.3301) -> (-10.1608, 89.3301) construction
  line L843 (-21.9812, 87.3094) -> (-18.321, 85.1962)
  line L844 (-82.4428, 25.866) -> (-86.603, 23.4641)
  line L845 (-9.6608, 90.1962) -> (-9.6608, 94.4226)
  line L846 (-0.5005, 10.866) -> (-0.5005, 20.866)
  line L847 (-73.7825, 20.866) -> (-82.4428, 25.866)
  line L848 (-26.9813, 26.7321) -> (-18.321, 21.7321)
  line L849 (-86.603, 50) -> (-0.0005, 100)
  line L850 (-8.6608, 68.4641) -> (-8.6608, 58.4641)
  line L851 (-36.6415, 73.4641) -> (-45.3018, 68.4641)
  line L852 (-55.462, 52.5981) -> (-64.1223, 57.5981)
  line L853 (-46.3018, 58.4641) -> (-46.3018, 68.4641)
  line L854 (-45.8018, 69.3301) -> (-46.3018, 68.4641) construction
  line L855 (-0.5005, 74.3301) -> (-0.5005, 84.3301)
  line L856 (-45.8018, 57.5981) -> (-54.462, 52.5981)
  line L857 (-17.821, 84.3301) -> (-17.821, 74.3301)
  line L858 (-9.6608, 58.4641) -> (-9.6608, 68.4641)
  line L859 (-8.6608, 26.7321) -> (-0.0005, 21.7321)
  line L860 (-17.821, 20.866) -> (-18.321, 21.7321) construction
  line L861 (-27.4813, 37.5981) -> (-18.821, 42.5981)
  line L862 (-64.1223, 57.5981) -> (-72.7825, 52.5981)
  line L863 (-45.3018, 68.4641) -> (-45.8018, 69.3301) construction
  line L864 (-27.9813, 58.4641) -> (-27.9813, 68.4641)
  line L865 (-63.6223, 63.2679) -> (-63.6223, 58.4641)
  line L866 (0.4996, 74.3301) -> (0.4996, 84.3301)
  line L867 (-8.6608, 36.7321) -> (-8.6608, 26.7321)
  line L868 (-26.9813, 36.7321) -> (-26.9813, 26.7321)
  line L869 (-72.7825, 52.5981) -> (-73.2825, 53.4641) construction
  line L870 (-18.321, 41.7321) -> (-26.9813, 36.7321)
  line L871 (-54.962, 53.4641) -> (-46.3018, 58.4641)
  line L872 (-45.3018, 68.4641) -> (-45.3018, 58.4641)
  line L873 (-37.1415, 52.5981) -> (-45.8018, 57.5981)
  line L874 (-73.2825, 53.4641) -> (-83.2825, 53.4641) construction
  line L875 (-8.6608, 90.1962) -> (-0.0005, 85.1962)
  line L876 (-8.6607, 58.4641) -> (-8.6607, 68.4641)
  line L877 (-36.1415, 52.5981) -> (-37.1415, 52.5981) construction
  line L878 (-27.4813, 69.3301) -> (-18.821, 74.3301)
  line L879 (-9.1608, 37.5981) -> (-0.5005, 42.5981)
  line L880 (-72.7825, 52.5981) -> (-73.7825, 52.5981) construction
  line L881 (-37.1415, 74.3301) -> (-37.1415, 78.5566)
  line L882 (-9.1608, 37.5981) -> (-19.1608, 37.5981) construction
  line L883 (-73.2825, 53.4641) -> (-64.6223, 58.4641)
  line L884 (-64.6223, 58.4641) -> (-64.6223, 62.6906)
  line L885 (-49.462, 71.4434) -> (-45.8018, 69.3301)
  line L886 (-73.7825, 52.5981) -> (-77.9428, 55)
  line L887 (-0.5005, 20.866) -> (-9.1608, 25.866)
  line L888 (-27.4813, 25.866) -> (-36.1415, 20.866)
  line L889 (-36.1415, 20.866) -> (-37.1415, 20.866) construction
  line L890 (-17.821, 20.866) -> (-18.821, 20.866) construction
  line L891 (-18.321, 21.7321) -> (-9.6608, 26.7321)
  line L892 (-27.4813, 37.5981) -> (-37.4813, 37.5981) construction
  line L893 (-0.0004, 21.7321) -> (-8.6607, 26.7321)
  line L894 (-36.6415, 21.7321) -> (-27.9813, 26.7321)
  line L895 (-27.9813, 26.7321) -> (-27.9813, 36.7321)
  line L896 (-46.3018, 68.4641) -> (-45.3018, 68.4641) construction
  line L897 (-72.7825, 52.5981) -> (-73.7825, 52.5981) construction
  line L898 (-45.3018, 58.4641) -> (-36.6415, 53.4641)
  line L899 (-8.6607, 36.7321) -> (-0.0004, 41.7321)
  line L900 (-46.3018, 68.4641) -> (-50.462, 70.866)
  line L901 (-17.821, 42.5981) -> (-9.1608, 37.5981)
  line L902 (-76.9428, 55.5773) -> (-73.2825, 53.4641)
  line L903 (-63.6223, 58.4641) -> (-54.962, 53.4641)
  line L904 (-9.6608, 36.7321) -> (-18.321, 41.7321)
  line L905 (-8.6608, 36.7321) -> (-9.1608, 37.5981) construction
  line L906 (-36.1415, 52.5981) -> (-36.6415, 53.4641) construction
  line L907 (-9.1608, 25.866) -> (-17.821, 20.866)
  line L908 (-36.1415, 79.1339) -> (-36.1415, 74.3301)